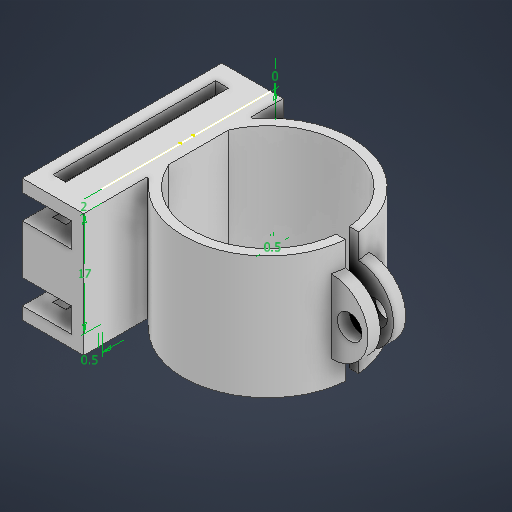
# Autodesk Inventor part: lygteholderv2
Saved by Autodesk Inventor 2026.1 (Build 301233020, 233B)
## iProperties
Created: 2026-03-21
Part Number: lygteholderv2
Material: Generic
Document SubType Name: Modeling
Designer: runek
Density: 1 g/cm^3
Appearance: Default
Author: runek
Autodesk Inventor part; units mm, degrees
ref_plane "YZ Plane" through (0, 0, 0) normal (1, 0, 0) x (0, 1, 0)
ref_plane "XZ Plane" through (0, 0, 0) normal (0, 1, 0) x (-1, 0, 0)
ref_plane "XY Plane" through (0, 0, 0) normal (0, 0, 1) x (1, 0, 0)
sketch "Sketch1" plane through (0, 0, 0) normal (0, 1, 0) x (-1, 0, 0)
  circle A0 centre (0, 0) radius 12.25
  circle A1 centre (0, 0) radius 13.75
  line L0 (0, 0) -> (-12.2034, 1.0677)
  line L1 (0, 0) -> (12.25, 0) construction
  line L2 (0, 0) -> (-12.2034, -1.0677)
  line L3 (0, 0) -> (12.25, 0) construction
  line L4 (-12.2034, 1.0677) -> (-20.2034, 1.0677)
  line L5 (-20.2034, 1.0677) -> (-20.2034, 3.0677)
  line L6 (-20.2034, 3.0677) -> (-12.2034, 3.0677)
  line L7 (-12.2034, 3.0677) -> (-12.2034, 1.0677)
  line L8 (0, 0) -> (0, -13.75)
  line L9 (0, 0) -> (-13.75, 0)
  line L10 (-12.25, 0) -> (-15.9581, 0)
  line L11 (-12.2034, -1.0677) -> (-20.2034, -1.0677)
  line L12 (-20.2034, -1.0677) -> (-20.2034, -3.0677)
  line L13 (-20.2034, -3.0677) -> (-12.2034, -3.0677)
  line L14 (-12.2034, -3.0677) -> (-12.2034, -1.0677)
  line L15 (12.25, 0) -> (12.25, 12)
  line L16 (12.25, 0) -> (12.25, -12)
  line L17 (12.25, -12) -> (13.25, -12)
  line L18 (13.25, -12) -> (13.25, 12)
  line L19 (13.25, 12) -> (12.25, 12)
  line L20 (12.25, 12) -> (12.25, -12)
  line L21 (0, 0) -> (13.25, 0)
  arc A2 (10.5917, 8.768) -> (12.25, 8.6251) centre (11.4912, 9.5126) ccw
  arc A3 (12.25, -8.6251) -> (10.5917, -8.768) centre (11.4912, -9.5126) ccw
  point P0 (12.25, 12)
  point P1 (-13.4034, 3.0677)
  point P2 (-13.4034, -3.0677)
  point P3 (12.25, -8.6251)
  point P4 (-13.7085, 1.0677)
  point P5 (-13.7085, -1.0677)
  dimension "d0" = 24.5
  dimension "d1" = 27.5
  dimension "d2" = 175
  dimension "d3" = 185
  dimension "d4" = 8
  dimension "d5" = 2
  dimension "d24" = 24
  constraints: 44 end point, 10 point on circle, 6 symmetric about line, 4 centre point, 4 horizontal, 4 parallel, 4 point on line, 3 perpendicular, 3 tangent, 2 coincident, 2 equal length, 2 vertical, 1 midpoint, 1 other
  measures "d0" diameter of A0
  measures "d1" diameter of A1
  measures "d2" angle of L1 L0
  measures "d4" distance of L5.end L6.end
  measures "d5" distance of L4.end L5.end
  measures "d24" distance of L19.end L16.end
extrude "Extrusion1" add sketch "Sketch1" along normal blind 20 contours L16 A1 L8 A0 | A0 L7 L6 A1 L15 | L21 L18 A1 L16 | L15 A1 L18 L21 | L4 A1 L6 L7 | L8 A1 L13 L14 A0 | L15 L19 L18 A1 | A1 A2 L15 | L16 A3 A1 | A1 L18 L17 L16 | L4 L5 L6 A1 | L14 L13 A1 L11 | A1 L13 L12 L11
sketch "Sketch5" plane through (20.2034, 0, -3.0677) normal (0, 0, -1) x (-1, 0, 0)
  line L0 (0, 0) -> (0, 20) projected
  line L1 (0, 10) -> (6.8, 10)
  line L2 (6.8, 0) -> (6.8, 20) projected
  circle A0 centre (6.8, 10) radius 6
  line L3 (0.8, 10) -> (3.8, 10)
  circle A1 centre (3.8, 10) radius 2
  line L4 (6.8, 20) -> (0, 20) projected
  line L5 (0, 20) -> (6.8, 20)
  line L6 (6.8, 20) -> (6.8, 0)
  line L7 (6.8, 0) -> (0, 0)
  line L8 (0, 0) -> (0, 20)
  point P0 (20.2034, 0)
  point P1 (6.8, 4)
  point P2 (6.8, 16)
  point P3 (0, 7.8789)
  point P4 (0, 12.1211)
  dimension "d13" = 12
  dimension "d14" = 3
  dimension "d15" = 4
  constraints: 12 end point, 2 coincident, 2 midpoint, 2 parallel, 2 point on line, 1 centre point, 1 horizontal, 1 perpendicular, 3 other
  measures "d14" distance of L3.start L3.end
  measures "d15" diameter of A1
extrude "Extrusion3" cut sketch "Sketch5" against normal blind 10 contours L0 L1 A0 L2 L7 | L0 L4 L2 A0 L1 | A0 L2 L1 A1 | L1 A1 L2 A0 | A1 L1 | L1 A1
sketch "Sketch6" plane through (-13.25, 0, -12) normal (-1, 0, 0) x (0, 0, 1)
  line L0 (-1.75, 0) -> (-1.75, 20) projected
  line L1 (25.75, 0) -> (25.75, 20) projected
  line L2 (-1.75, 20) -> (25.75, 20)
  line L3 (25.75, 20) -> (25.75, 18)
  line L4 (25.75, 18) -> (-1.75, 18)
  line L5 (-1.75, 18) -> (-1.75, 20)
  line L6 (-1.75, 20) -> (25.75, 20) projected
  line L7 (-1.75, 18) -> (25.75, 18)
  line L8 (25.75, 18) -> (25.75, 1)
  line L9 (25.75, 1) -> (-1.75, 1)
  line L10 (-1.75, 1) -> (-1.75, 18)
  line L11 (12, 0) -> (12, 20)
  line L12 (-0.25, 20) -> (24.25, 20) projected
  line L13 (25.75, 1) -> (26.25, 1)
  line L14 (26.25, 1) -> (26.25, 0)
  line L15 (26.25, 0) -> (25.75, 0)
  line L16 (25.75, 0) -> (25.75, 1)
  line L17 (-1.75, 1) -> (-2.25, 1)
  line L18 (-2.25, 1) -> (-2.25, 0)
  line L19 (-2.25, 0) -> (-1.75, 0)
  line L20 (-1.75, 0) -> (-1.75, 1)
  line L21 (-1.75, 1) -> (25.75, 1)
  line L22 (25.75, 1) -> (25.75, 0)
  line L23 (25.75, 0) -> (-1.75, 0)
  line L24 (-1.75, 0) -> (-1.75, 1)
  point P0 (-1.75, 18)
  point P1 (13.0677, 20)
  point P2 (10.9323, 20)
  point P3 (-1.75, 0)
  point P4 (-1.75, 1)
  dimension "d18" = 2
  dimension "d21" = 0
  dimension "d22" = 17
  dimension "d25" = 0.5
  dimension "d26" = 0.5
  constraints: 42 end point, 10 parallel, 5 horizontal, 5 perpendicular, 3 point on line, 1 midpoint
  measures "d18" distance of L2.end L3.end
  measures "d21" distance between parallel lines of L2 L6
  measures "d22" distance of L7.end L8.end
  measures "d25" distance of L14.end L15.end
  measures "d26" distance of L19.end L18.end
extrude "Extrusion5" add sketch "Sketch6" against normal blind 2
extrude "Extrusion9" add sketch "Sketch1" along normal blind 20 contours L4 L5 L6 A1 | L14 L13 A1 L11 | A1 L13 L12 L11
extrude "Extrusion10" cut sketch "Sketch5" against normal blind 10 contours L0 L1 A0 L2 L7 | L0 L4 L2 A0 L1 | A1 L1 | L1 A1
extrude "Extrusion12" add sketch "Sketch1" along normal blind 20 contours L4 A1 L6 L7 | L14 L13 A1 L11
sketch "Sketch14" plane through (-13.25, 1, 13.75) normal (0, 0, 1) x (1, 0, 0)
  line L0 (0, -1) -> (2, -1) projected
  line L1 (2, 19) -> (2, -1) projected
  line L2 (0, -1) -> (2, -1)
  line L3 (2, -1) -> (2, 19)
  line L4 (2, 19) -> (0, 19)
  line L5 (0, 19) -> (0, -1)
  point P0 (13.25, -1)
  constraints: 8 end point, 2 parallel, 1 horizontal, 1 perpendicular
extrude "Extrusion14" add sketch "Sketch14" along normal blind 5
sketch "Sketch15" plane through (-13.25, 1, -13.75) normal (-1, 0, 0) x (0, 0, 1)
  line L0 (32.5, 19) -> (0, 19) projected
  line L1 (0, -1) -> (0, 19) projected
  line L2 (32.5, 19) -> (0, 19)
  line L3 (0, 19) -> (0, 17)
  line L4 (0, 17) -> (32.5, 17)
  line L5 (32.5, 17) -> (32.5, 19)
  line L6 (0, 17) -> (32.5, 17)
  line L7 (32.5, 17) -> (32.5, 13)
  line L8 (32.5, 13) -> (0, 13)
  line L9 (0, 13) -> (0, 17)
  line L10 (32.5, -1) -> (0, -1)
  line L11 (0, -1) -> (0, 1)
  line L12 (0, 1) -> (32.5, 1)
  line L13 (32.5, 1) -> (32.5, -1)
  line L14 (0, 1) -> (32.5, 1)
  line L15 (32.5, 1) -> (32.5, 5)
  line L16 (32.5, 5) -> (0, 5)
  line L17 (0, 5) -> (0, 1)
  line L18 (32.5, 5) -> (0, 5)
  line L19 (0, 5) -> (0, 13)
  line L20 (0, 13) -> (32.5, 13)
  line L21 (32.5, 13) -> (32.5, 5)
  point P0 (13.75, -1)
  point P1 (0, 1)
  dimension "d57" = 2
  dimension "d58" = 4
  dimension "d59" = 2
  dimension "d60" = 4
  constraints: 40 end point, 10 parallel, 5 horizontal, 5 perpendicular, 5 point on line
  measures "d57" distance of L3.end L2.end
  measures "d58" distance of L6.end L7.end
  measures "d59" distance of L10.end L11.end
  measures "d60" distance of L15.end L14.end
extrude "Extrusion15" add sketch "Sketch15" along normal blind 8 contours L5 L4 L1 L0 | L21 L16 L1 L8 | L13 L10 L1 L12
sketch "Sketch16" plane through (0, 0, 0) normal (0, -1, 0) x (1, 0, 0)
  line L0 (-11.25, 18.75) -> (-21.25, 18.75) projected
  line L1 (-21.25, -13.75) -> (-19.25, -13.75)
  line L2 (-19.25, -13.75) -> (-19.25, 18.75)
  line L3 (-19.25, 18.75) -> (-21.25, 18.75)
  line L4 (-21.25, 18.75) -> (-21.25, -13.75)
  line L5 (-19.25, -13.75) -> (-17.15, -13.75)
  line L6 (-17.15, -13.75) -> (-17.15, 18.75)
  line L7 (-17.15, 18.75) -> (-19.25, 18.75)
  line L8 (-19.25, 18.75) -> (-19.25, -13.75)
  line L9 (-19.25, 18.75) -> (-17.15, 18.75)
  line L10 (-17.15, 18.75) -> (-17.15, 15.75)
  line L11 (-17.15, 15.75) -> (-19.25, 15.75)
  line L12 (-19.25, 15.75) -> (-19.25, 18.75)
  line L13 (-19.25, -13.75) -> (-17.15, -13.75)
  line L14 (-17.15, -13.75) -> (-17.15, -10.75)
  line L15 (-17.15, -10.75) -> (-19.25, -10.75)
  line L16 (-19.25, -10.75) -> (-19.25, -13.75)
  point P0 (0, 0)
  dimension "d63" = 2
  dimension "d64" = 2.1
  dimension "d65" = 3
  dimension "d66" = 3
  constraints: 32 end point, 8 parallel, 4 horizontal, 4 perpendicular, 4 point on line
  measures "d63" distance of L3.end L2.end
  measures "d64" distance of L7.end L6.end
  measures "d65" distance of L9.end L10.end
  measures "d66" distance of L14.end L13.end
extrude "Extrusion16" cut sketch "Sketch16" against normal blind 20 contours L6 L15 L2 L11
body "Solid1"
